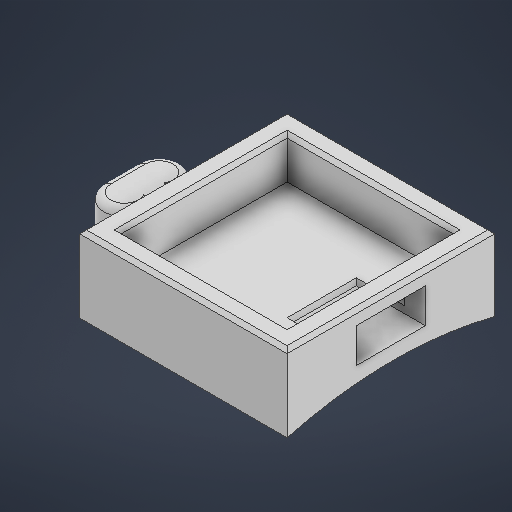
# Autodesk Inventor part: depth_sensor_support
Saved by Autodesk Inventor 2026.2 (Build 302298010, 298A)
## iProperties
Created: 2026-11-03
Part Number: depth_sensor_support
Material: Générique
Document SubType Name: Modeling
Designer: User
Density: 1 g/cm^3
Appearance: Par défaut
Author: User
Autodesk Inventor part; units mm, degrees
ref_plane "YZ Plane" through (0, 0, 0) normal (1, 0, 0) x (0, 1, 0)
ref_plane "XZ Plane" through (0, 0, 0) normal (0, 1, 0) x (-1, 0, 0)
ref_plane "XY Plane" through (0, 0, 0) normal (0, 0, 1) x (1, 0, 0)
sketch "Esquisse1" plane through (0, 0, 0) normal (0, 1, 0) x (-1, 0, 0)
  line L0 (9.3365, 15.3318) -> (-20.6635, 15.3318)
  line L1 (-20.6635, 15.3318) -> (-20.6635, -14.6682)
  line L2 (-20.6635, -14.6682) -> (9.3365, -14.6682)
  line L3 (9.3365, -14.6682) -> (9.3365, 15.3318)
  point P0 (0, 0)
  dimension "d0" = 30
  dimension "d1" = 30
  constraints: 8 end point, 2 parallel, 1 horizontal, 1 perpendicular
  measures "d0" distance of L2.end L0.start
  measures "d1" distance of L1.end L2.end
extrude "Extrusion1" add sketch "Esquisse1" along normal blind 3
sketch "Esquisse2" plane through (0, 3, 0) normal (0, 1, 0) x (1, 0, 0)
  line L0 (17.6635, 11.6682) -> (-6.3365, 11.6682)
  line L1 (-6.3365, 11.6682) -> (-6.3365, -12.3318)
  line L2 (-6.3365, -12.3318) -> (17.6635, -12.3318)
  line L3 (17.6635, -12.3318) -> (17.6635, 11.6682)
  line L4 (-9.3365, 14.6682) -> (-9.3365, -15.3318) projected
  line L5 (-9.3365, -15.3318) -> (20.6635, -15.3318) projected
  line L6 (20.6635, 14.6682) -> (-9.3365, 14.6682) projected
  line L7 (20.6635, -15.3318) -> (20.6635, 14.6682) projected
  line L8 (20.6635, -15.3318) -> (20.6635, 14.6682) projected
  line L9 (20.6635, 14.6682) -> (-9.3365, 14.6682) projected
  line L10 (-9.3365, 14.6682) -> (-9.3365, -15.3318) projected
  line L11 (-9.3365, -15.3318) -> (20.6635, -15.3318) projected
  point P0 (0, 0)
  dimension "d4" = 24
  dimension "d5" = 24
  dimension "d6" = 3
  dimension "d8" = 3
  constraints: 8 end point, 2 parallel, 1 horizontal, 1 perpendicular
  measures "d4" distance of L1.end L2.end
  measures "d5" distance of L0.end L1.end
  measures "d6" distance between parallel lines of L4 L1
  measures "d8" distance between parallel lines of L6 L0
extrude "Extrusion2" add sketch "Esquisse2" along normal blind 6
sketch "Esquisse3" plane through (-9.3365, 0, -14.6682) normal (-1, 0, 0) x (0, 0, 1)
  circle A0 centre (14.6682, -58.74) radius 58.74
  line L0 (30, 0) -> (0, 0) projected
  line L1 (0, 0) -> (0, -1.8609)
  line L2 (30, 0) -> (30, -2.0362)
  point P0 (14.6682, 0)
  point P1 (14.6682, 0)
  dimension "d11" = 0
  dimension "d12" = 117.48
  constraints: 4 end point, 2 point on circle, 1 centre point, 1 parallel, 1 tangent, 1 vertical
  measures "d11" horizontal distance of point (14.668, 0) A0.centre
  measures "d12" diameter of A0
extrude "Extrusion3" add sketch "Esquisse3" against normal up to surface (30 mm away) contours A0 L0 L2 | L1 L0 A0
sketch "Esquisse4" plane through (20.6635, 9, 15.3318) normal (1, 0, 0) x (0, 0, -1)
  line L0 (10, -2) -> (20, -2)
  line L1 (20, -2) -> (20, -7)
  line L2 (20, -7) -> (10, -7)
  line L3 (10, -7) -> (10, -2)
  line L4 (0, 0) -> (30, 0) projected
  line L5 (0, -11.0362) -> (0, 0) projected
  point P0 (15.3318, -9)
  point P1 (15, -2)
  dimension "d15" = 10
  dimension "d16" = 5
  dimension "d17" = 2
  dimension "d18" = 10
  constraints: 8 end point, 2 parallel, 1 horizontal, 1 midpoint, 1 perpendicular
  measures "d15" distance of L0.start L0.end
  measures "d16" distance of L0.end L1.end
  measures "d17" distance from line of L4 point (15, -2)
  measures "d18" distance between parallel lines of L5 L3
extrude "Extrusion4" cut sketch "Esquisse4" against normal blind 10
sketch "Esquisse5" plane through (0, 0, 0) normal (0, 1, 0) x (-1, 0, 0)
  line L0 (9.3365, -2.1682) -> (15.3365, -2.1682)
  line L1 (15.3365, -2.1682) -> (15.3365, 2.8318)
  line L2 (15.3365, 2.8318) -> (9.3365, 2.8318)
  line L3 (9.3365, 2.8318) -> (9.3365, -2.1682)
  line L4 (15.3365, -2.1682) -> (15.3365, 2.8318) construction
  line L5 (18.3365, -2.1682) -> (18.3365, 2.8318)
  line L6 (12.3365, 2.8318) -> (12.3365, -2.1682)
  arc A0 (12.3365, -2.1682) -> (18.3365, -2.1682) centre (15.3365, -2.1682) ccw
  arc A1 (18.3365, 2.8318) -> (12.3365, 2.8318) centre (15.3365, 2.8318) ccw
  line L7 (9.3365, -14.6682) -> (9.3365, 15.3318) projected
  line L8 (9.3365, 15.3318) -> (-20.6635, 15.3318) projected
  point P0 (0, 0)
  point P1 (15.3365, 0.3318)
  dimension "d21" = 5
  dimension "d22" = 6
  dimension "d23" = 0
  dimension "d24" = 12.5
  dimension "d25" = 3
  constraints: 16 end point, 4 point on circle, 4 tangent, 3 parallel, 2 centre point, 1 horizontal, 1 midpoint, 1 perpendicular, 1 vertical
  measures "d21" distance of L2.end L0.start
  measures "d22" distance of L1.end L2.end
  measures "d23" distance between parallel lines of L7 L3
  measures "d24" distance between parallel lines of L8 L2
  measures "d25" radius of A1
extrude "Extrusion5" add sketch "Esquisse5" along normal blind 4.5
fillet "Congé1" radius 1 5 edges at (-18.3365, 4.5, 0.3318) (-15.3365, 4.5, 5.8318) (-15.3365, 4.5, -5.1682) (-10.8365, 4.5, -2.1682) (-10.8365, 4.5, 2.8318)
chamfer "Chanfrein1" distance 0.5 angle 45 8 edges at (5.6635, 9, -14.6682) (-9.3365, 9, 0.3318) (20.6635, 9, 0.3318) (5.6635, 9, 15.3318) (5.6635, 9, -11.6682) (-6.3365, 9, 0.3318) (17.6635, 9, 0.3318) (5.6635, 9, 12.3318)
equation "\"d0\" = d1"
equation "\"e\" = 0.1 * d1"
equation "\"d4\" = d1 - 2 * e"
equation "\"d5\" = d1 - 2 * e"
equation "\"d6\" = e"
equation "\"d8\" = e"
equation "\"d15\" = 0.333333 * d1"
equation "\"d16\" = 0.5 * d15"
equation "\"d18\" = -0.5 * d15 + 0.5 * d1"
equation "\"d22\" = 2 * d25"
equation "\"d24\" = -0.5 * d21 + 0.5 * d1"
equation "\"d26\" = 0.5 * d9 + 0.5 * e"
equation "\"d9\" = 6"
